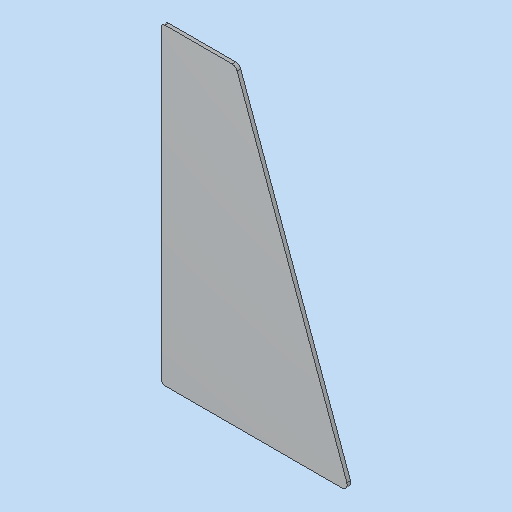
# Autodesk Inventor part: MM0948AN140_G01_111
Saved by Autodesk Inventor 2023.3 (Build 273359000, 359)
## iProperties
Created: 2023-03-23
Part Number: MM0948AN140_G01_111
Material: 3.3535 AlMg3 - AW 5754 (Blech)
Description: =<RBPARTNOTITLE2>
Document SubType Name: Blech
Designer: ric7an
Mass: 70.3195 g
Surface Area: 270.666 cm^2
Volume: 26.0539 cm^3
Density: 2.699 g/cm^3
Sheet Metal Rule: Standard_mm
Appearance: Aluminium AnP
AnP_Kategorie: 1
AnP_Material: =<Material>
MaxAbmaße: 2 x 176 x 104,8 (FM)
AnP_TemplVers: 20200821
RBDOCUMENTTYPE: DRF
RBDOCUMENTVERSION: 00
RBDRAWINGMAINSCALE: 1:1
RBDRAWINGMISSINGSPEC: --
RBDRAWINGVOLUME: --
RBDSV1: 0850
RBGBEDGESIN1: +0,5
RBGBEDGESIN2: +0,2
RBGBEDGESOUT1: -0,3
RBGBEDGESOUT2: -0,1
RBMATERIAL: =<Material>
RBMATMEETS: --
RBMATNO: =<Part Number>
RBPARTMADEOF: 2 x 176 x 104,8 (FM)
RBPARTNO: SIEHE MNR
RBPARTNOTITLE1: manufactured part
RBPARTNOTITLE2: Anfertigungsteil
RBPARTSAFETYINDICATOR: --
RBSURFACE: anodised grey
RBSURFACE2: eloxiert E6/EV1 aluminiumfarbig
RBZEDGESNORM: ISO13715:2002-06
RBZGENDIMCLASS: m
RBZGENDIMNORM: ISO 2768-1:1989-11
RBZGENGEOCLASS: H
RBZGENGEONORM: ISO 2768-2:1989-11
RBZSURFACENORM: ISO13D2:2002-02
RBZTOLERANCENORM: ISO 14405-1:2010-12
AnP_Kommentar_aktuell: =<Comments>
AnP_Material_aktuell: =<Material>
Author: FH/Wi
Keywords: =<RBPARTMADEOF>
Comments: =<RBSURFACE2>
Revision Number: 01
Autodesk Inventor part; units mm, degrees
ref_plane "YZ Plane" through (0, 0, 0) normal (1, 0, 0) x (0, 1, 0)
ref_plane "XZ Plane" through (0, 0, 0) normal (0, 1, 0) x (-1, 0, 0)
ref_plane "XY Plane" through (0, 0, 0) normal (0, 0, 1) x (1, 0, 0)
sketch "Skizze1" plane through (0, 0, 0) normal (0, 0, 1) x (1, 0, 0)
  line L0 (0, 0) -> (0, 176)
  line L1 (42.7441, 174.0261) -> (104.6191, 4.0261)
  arc A0 (101.8, 0) -> (104.6191, 4.0261) centre (101.8, 3) ccw
  line L2 (101.8, 0) -> (0, 0)
  line L3 (0, 176) -> (39.9251, 176)
  arc A1 (42.7441, 174.0261) -> (39.9251, 176) centre (39.9251, 173) ccw
  point P0 (42.0257, 176)
  dimension "d0" = 3
  dimension "d1" = 101.8
  dimension "d4" = 70
  dimension "d10" = 176
  dimension "d11" = 3
  measures "d0" radius of A0
  measures "d1" distance from line of L2.start L0
  measures "d4" angle of L2 L1
  measures "d10" distance of L0.start L0.end
  measures "d11" radius of A1
extrude "Grobblech2" add sketch "Skizze1" along normal blind 2
fillet "Rundung1" radius 2 2 edges at (0, 0, 1) (0, 176, 1)
equation "\"d6\" = Stärke"
equation "\"Biegeradius\" = Stärke"
equation "\"BreiteBiegungsfreistellung\" = Stärke"
equation "\"TiefeBiegungsfreistellung\" = 0.5 * Stärke"
equation "\"GrößeEckenfreistellung\" = 4 * Stärke"
equation "\"MinimalRest\" = 2 * Stärke"
equation "\"Übergangsradius\" = Biegeradius"
equation "\"JacobiRadiusGröße\" = Biegeradius"
equation "\"Abstandsgröße\" = Stärke"
equation "\"Stärke\" = 2"
